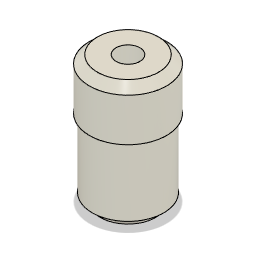
RSC_v4_1_1 (Autodesk Fusion 360 archive; units mm, degrees)
design "servo_shaft"
Autodesk Fusion 360 part; units mm, degrees
sketch "Sketch1" plane through (0, 0, 0) normal (0, 1, 0) x (1, 0, 0)
  circle A0 centre (0, 0) radius 2.425
  circle A1 centre (0, 0) radius 2.25
  circle A2 centre (0, 0) radius 0.75
  dimension "d1" = 4.85
  dimension "d2" = 4.5
  dimension "d9" = 1.5
  constraint coincident A0.centre A1.centre
  constraint concentric A0 A1
  constraint concentric A0 A2
  measures "d1" diameter of A0
  measures "d2" diameter of A1
  measures "d9" diameter of A2
extrude "Extrude1" add sketch "Sketch1" along normal blind 4.8 contours A1 | A2
extrude "Extrude2" add sketch "Sketch1" along normal blind 3.2 from surface at 4.8 contours A0 | A1 | A2
chamfer "Chamfer1" distance 0.5 angle 45 2 edges at (-2.2609, 8, 0.8769) (-2.0977, 0, 0.8136)
extrude "Extrude3" cut sketch "Sketch1" against normal blind 3 from surface at 8 contours A2

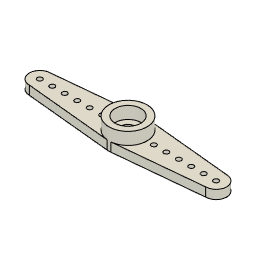
design "servo_horn"
Autodesk Fusion 360 part; units mm, degrees
sketch "Sketch1" plane through (0, 0, 0) normal (0, 1, 0) x (1, 0, 0)
  circle A0 centre (0, 0) radius 3.45
  line L0 (-0.3378, 3.4334) -> (-15.925, 1.9)
  line L1 (-15.925, 0) -> (0, 0) construction
  line L2 (0, -3.45) -> (0, 3.45) construction
  line L3 (-0.3378, -3.4334) -> (-15.925, -1.9)
  arc A1 (-15.925, 1.9) -> (-15.925, -1.9) centre (-15.925, 0) ccw
  line L4 (0.3378, -3.4334) -> (15.925, -1.9)
  arc A2 (15.925, -1.9) -> (15.925, 1.9) centre (15.925, 0) ccw
  line L5 (0.3378, 3.4334) -> (15.925, 1.9)
  circle A3 centre (-15.925, 0) radius 0.45
  circle A4 centre (-13.675, 0) radius 0.45
  circle A5 centre (-11.425, 0) radius 0.45
  circle A6 centre (-9.175, 0) radius 0.45
  circle A7 centre (-6.925, 0) radius 0.45
  circle A8 centre (-4.675, 0) radius 0.45
  circle A9 centre (4.675, 0) radius 0.45
  circle A10 centre (6.925, 0) radius 0.45
  circle A11 centre (9.175, 0) radius 0.45
  circle A12 centre (11.425, 0) radius 0.45
  circle A13 centre (13.675, 0) radius 0.45
  circle A14 centre (15.925, 0) radius 0.45
  circle A15 centre (0, 0) radius 1.225
  circle A16 centre (0, 0) radius 2.325
  point P0 (-15.475, 0)
  point P1 (-14.125, 0)
  dimension "d1" = 6.9
  dimension "d2" = 15.925
  dimension "d3" = 1.9
  dimension "d4" = 0.9
  dimension "d10" = 2.25
  dimension "d11" = 2.25
  dimension "d12" = 2.25
  dimension "d13" = 2.25
  dimension "d14" = 2.45
  dimension "d17" = 4.65
  dimension "d20" = 2.25
  constraint coincident A0.centre L1.end
  constraint coincident A0 L0.start
  constraint horizontal L1
  constraint coincident A0 L2.start
  constraint coincident A0 L2.end
  constraint perpendicular L1 L2
  constraint midpoint A0.centre L2
  constraint tangent A0 L0
  constraint vertical L0.end L1.start
  constraint symmetric L0.end L1 L3.end
  constraint coincident L1.start A1.centre
  constraint symmetric L0.start L2 L5.start
  constraint symmetric L0.end L2 A2.end
  constraint symmetric L2 L3.start L4.start
  constraint symmetric L2 L3.end L4.end
  constraint symmetric L2 A1 A2
  constraint concentric A1 A3
  constraint coincident L1 P0
  constraint coincident A3 P0
  constraint coincident L1 P1
  constraint coincident L1 A4.centre
  constraint coincident P1 A4
  constraint equal A3 A4
  constraint coincident L1 A5.centre
  constraint coincident L1 A6.centre
  constraint equal A4 A5
  constraint equal A5 A6
  constraint equal A7 A8
  constraint equal A6 A7
  constraint coincident L1 A7.centre
  constraint coincident L1 A8.centre
  constraint symmetric L2 A3 A14
  constraint symmetric L2 A4 A13
  constraint symmetric L2 A5 A12
  constraint symmetric L2 A6 A11
  constraint symmetric L2 A7 A10
  constraint symmetric L2 A8 A9
  constraint coincident A0 L3.start
  constraint tangent A0 L3
  measures "d1" diameter of A0
  measures "d2" distance of L1.start A0.centre
  measures "d3" vertical distance of L0.end L1.start
  measures "d4" diameter of A3
  measures "d10" distance of A4.centre A5.centre
  measures "d11" distance of A5.centre A6.centre
  measures "d12" distance of A6.centre A7.centre
  measures "d13" distance of A7.centre A8.centre
  measures "d14" diameter of A15
  measures "d17" diameter of A16
  measures "d20" distance of L1.start A4.centre
extrude "Extrude1" add sketch "Sketch1" along normal blind 1.6 contours A0 | A0 L4 A2 L5 | A0 L0 L3 A1 | A16
extrude "Extrude2" add sketch "Sketch1" along normal blind 3.8 contours A0
extrude "Extrude3" cut sketch "Sketch1" along normal blind 1.1 contours A16
named bodies: "servo_horn"
